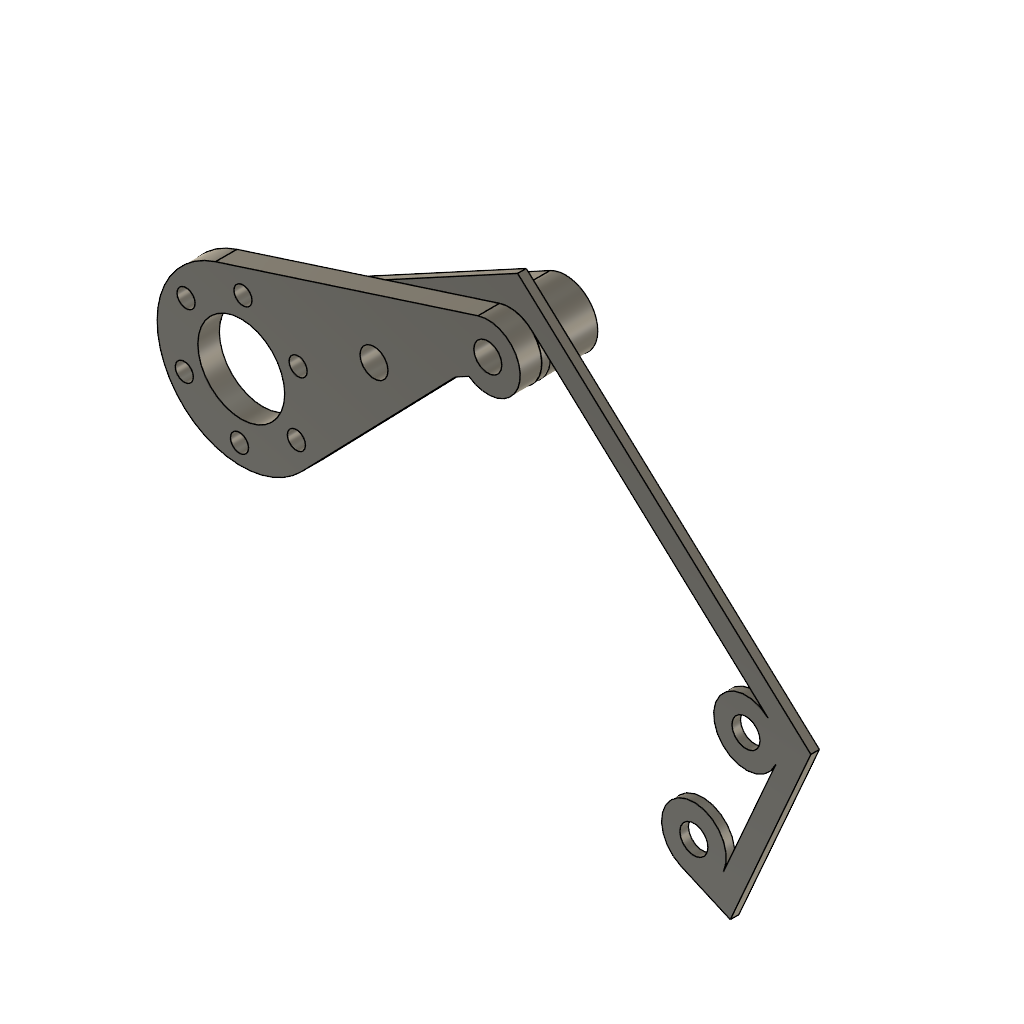
Chairwheelmotor (Autodesk Fusion 360 design; units mm, degrees)
Autodesk Fusion 360 part; units mm, degrees
sketch "Sketch1" plane through (0, 0, 0) normal (0, 1, 0) x (1, 0, 0)
  circle A0 centre (0, 0) radius 8.5
  line L0 (0, 0) -> (0, -8.5) construction
  line L1 (-3, -7.953) -> (3, -7.953)
  line L2 (3, -7.953) -> (3, -5.1)
  line L3 (3, -5.1) -> (-3, -5.1)
  line L4 (-3, -5.1) -> (-3, -7.953)
  circle A1 centre (0, -55) radius 3.25
  circle A2 centre (42.7417, 22.9215) radius 3.25
  circle A3 centre (54.812, -4.5432) radius 3.25
  circle A4 centre (-26.3738, -40.7023) radius 3.25
  line L5 (0, 0) -> (0, -55) construction
  line L6 (-26.3738, -40.7023) -> (0, -55) construction
  circle A5 centre (-26.3738, -40.7023) radius 7.5
  circle A6 centre (0, -55) radius 7.5
  circle A7 centre (54.812, -4.5432) radius 7.5
  circle A8 centre (42.7417, 22.9215) radius 7.5
  circle A9 centre (0, 0) radius 13.5
  line L7 (-29.9482, -47.2957) -> (-3.5744, -61.5934)
  line L8 (5.0795, -60.518) -> (59.8916, -10.0612)
  line L9 (61.6782, -1.5256) -> (49.6079, 25.9391)
  line L10 (-32.9672, -37.1278) -> (-38.9246, -48.1169)
  line L11 (-38.9246, -48.1169) -> (1.8946, -70.2458)
  line L12 (1.8946, -70.2458) -> (69.8492, -7.6907)
  line L13 (69.8492, -7.6907) -> (51.1678, 34.8169)
  line L14 (51.1678, 34.8169) -> (39.7242, 29.7876)
  line L15 (1.5489, -52.1428) -> (-24.8248, -37.8451)
  line L16 (-26.3738, -40.7023) -> (-57.1431, -24.0216) construction
  circle A10 centre (-57.1431, -24.0216) radius 10.05
  circle A11 centre (-57.1431, -24.0216) radius 19.5
  line L17 (0, -55) -> (-43.1348, -10.4563)
  line L18 (-63.1121, -42.5856) -> (-2.2957, -62.14)
  arc A12 (-20.666, -35.8369) -> (1.5489, -52.1428) centre (24.9957, 3.0862) ccw
  circle A13 centre (-57.1431, -24.0216) radius 15 construction
  circle A14 centre (-43.9563, -31.1705) radius 2.1
  circle A15 centre (-44.3586, -16.1759) radius 2.1
  circle A16 centre (-57.5455, -9.027) radius 2.1
  circle A17 centre (-70.33, -16.8727) radius 2.1
  circle A18 centre (-69.9277, -31.8673) radius 2.1
  circle A19 centre (-56.7408, -39.0162) radius 2.1
  dimension "d1" = 17
  dimension "d3" = 6
  dimension "d4" = 6.5
  dimension "d5" = 6.5
  dimension "d6" = 6.5
  dimension "d7" = 6.5
  dimension "d8" = 5.1
  dimension "d9" = 55
  dimension "d10" = 30
  dimension "d11" = 48.5
  dimension "d12" = 30
  dimension "d13" = 55
  dimension "d14" = 48.5
  dimension "d15" = 74.5
  dimension "d16" = 93.9411
  dimension "d17" = 4.25
  dimension "d18" = 4.25
  dimension "d19" = 4.25
  dimension "d20" = 4.25
  dimension "d21" = 5
  dimension "d22" = 5
  dimension "d23" = 5
  dimension "d24" = 5
  dimension "d27" = 35
  dimension "d28" = 20.1
  dimension "d29" = 39
  dimension "d34" = 60
  dimension "d35" = 30
  dimension "d36" = 4.2
  dimension "d38" = 360
  constraint coincident A0.centre L0.start
  constraint coincident A0 L0.end
  constraint vertical L0
  constraint horizontal L1
  constraint vertical L2
  constraint horizontal L3
  constraint vertical L4
  constraint coincident A0 L1.start
  constraint symmetric L0 L2 L4
  constraint parallel L0 L5
  constraint coincident A1.centre L5.end
  constraint coincident A4.centre L6.start
  constraint coincident A5 L7.start
  constraint coincident A6 L7.end
  constraint tangent A6 L7
  constraint coincident A6 L8.start
  constraint coincident A7 L8.end
  constraint coincident A7 L9.start
  constraint coincident A8 L9.end
  constraint tangent A6 L8
  constraint tangent A7 L8
  constraint tangent A7 L9
  constraint tangent A8 L9
  constraint tangent A5 L7
  constraint coincident A5 L10.start
  constraint perpendicular L7 L10
  constraint coincident A8 L14.end
  constraint tangent A8 L14
  constraint tangent A5 L10
  constraint parallel L7 L11
  constraint parallel L8 L12
  constraint parallel L9 L13
  constraint perpendicular L13 L14
  constraint coincident A1 L15.start
  constraint coincident A4 L15.end
  constraint tangent A4 L15
  constraint tangent A1 L15
  constraint parallel L6 L16
  constraint coincident L16.end A10.centre
  constraint coincident A11 L17.end
  constraint tangent A11 L17
  constraint coincident A11 L18.start
  constraint coincident A6 L18.end
  constraint tangent A6 L18
  constraint tangent A11 L18
  constraint coincident A5 A12.start
  constraint tangent A5 A12
  constraint concentric A10 A13
  constraint coincident A13 A14.centre
  constraint coincident L16 A14.centre
  measures "d1" diameter of A0
  measures "d3" distance of L2 L4
  measures "d4" diameter of A1
  measures "d5" diameter of A2
  measures "d6" diameter of A3
  measures "d7" diameter of A4
  measures "d8" distance of A0.centre L3
  measures "d9" distance of A0.centre A1.centre
  measures "d11" distance of A0.centre A4.centre
  measures "d12" distance of A2.centre A3.centre L2.end
  measures "d13" distance of A0.centre A3.centre
  measures "d14" distance of A0.centre A2.centre L2.end
  measures "d15" distance of A1.centre A3.centre
  measures "d16" distance of A2.centre A4.centre
  measures "d22" distance of L7 L11
  measures "d23" distance of L8 L12
  measures "d24" distance of L9 L13
  measures "d27" distance of A4.centre L16.end
  measures "d28" diameter of A10
  measures "d29" diameter of A11
  measures "d34" radius of A12
  measures "d35" diameter of A13
  measures "d36" diameter of A14
extrude "Extrude1" add sketch "Sketch1" along normal blind 2 contours A1 A6 L15 L17 | A1 A6 L15 A12 | A1 A6 L17 A12 | A5 A6 L7 L10 L11 L18 | A6 A7 A8 L8 L9 L11 L12 L13 L14 L18 | A5 | A7 | A8 makes body 1
extrude "Extrude2" add sketch "Sketch1" against normal blind 5 separate body contours A1 A6 L15 L17 | A1 A6 L15 A12 | A1 A6 L17 A12 | A6 L15 L17 A12 | A6 L17 A12 | A5 A6 L7 L15 L17 A12 | L15 L17 A12 | A5 L10 L11 L15 A11 L17 L18 A12 | A5 A6 L7 L10 L11 L18 | A5 L15 A12 | A11 | A5 makes body 2
extrude "Extrude3" add sketch "Sketch1" along normal blind 13 separate body contours A1 A6 L15 L17 | A1 A6 L15 A12 | A1 A6 L17 A12 | A6 L17 A12 | A5 A6 L7 L15 L17 A12 | A5 L15 A12 | A5 makes body 3
equation "d5 = d4"
equation "d6 = d4"
equation "d7 = d4"
equation "d12 = d10"
equation "d14 = d11"
equation "d23 = d22"
equation "d24 = d22"
